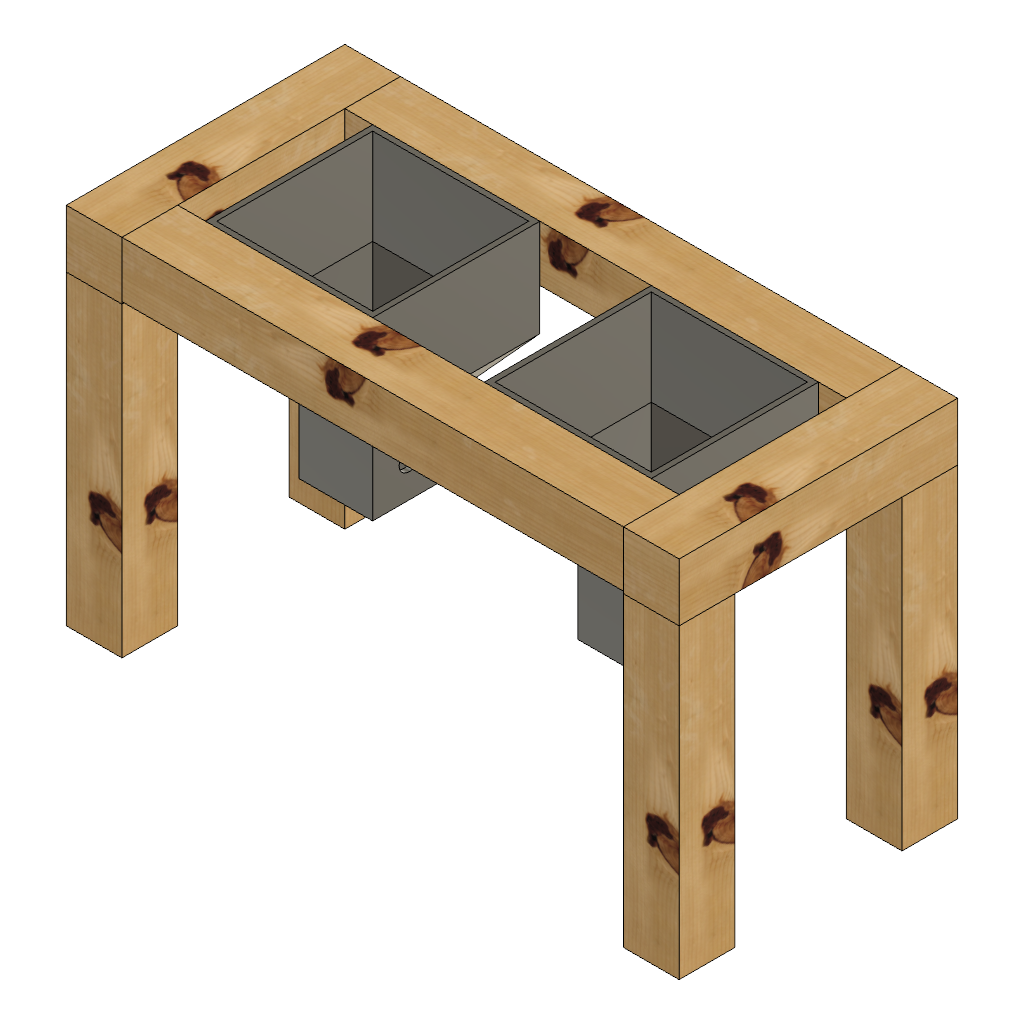
Hopper Mockup (Autodesk Fusion 360 design; units mm, degrees)
Autodesk Fusion 360 part; units mm, degrees
sketch "Sketch1" plane through (0, 0, 0) normal (0, 0, 1) x (1, 0, 0)
  line L0 (-76.2, 76.2) -> (76.2, 76.2)
  line L1 (76.2, 76.2) -> (76.2, -76.2)
  line L2 (76.2, -76.2) -> (-76.2, -76.2)
  line L3 (-76.2, -76.2) -> (-76.2, 76.2)
  line L4 (-76.2, 76.2) -> (76.2, -76.2) construction
  line L5 (76.2, 76.2) -> (-76.2, -76.2) construction
  dimension "d1" = 152.4
  dimension "d2" = 152.4
  constraint horizontal L0
  constraint perpendicular L0 L1
  constraint parallel L0 L2
  constraint parallel L1 L3
  constraint coincident L4 origin
  constraint coincident L5 origin
  measures "d1" distance of L0.start L0.end
  measures "d2" distance of L0.start L2.end
extrude "Extrude1" add sketch "Sketch1" against normal blind 88.9 makes body 1
sketch "Sketch2" plane through (0, 0, -88.9) normal (0, 0, -1) x (1, 0, 0)
  line L0 (76.2, 76.2) -> (-76.2, 76.2)
  line L1 (-76.2, 76.2) -> (-76.2, -76.2)
  line L2 (-76.2, -76.2) -> (76.2, -76.2)
  line L3 (76.2, -76.2) -> (76.2, 76.2)
  line L4 (-76.2, 76.2) -> (76.2, 76.2)
  line L5 (76.2, 76.2) -> (76.2, -76.2)
  line L6 (76.2, -76.2) -> (-76.2, -76.2)
  line L7 (-76.2, -76.2) -> (-76.2, 76.2)
  constraint horizontal L4
  constraint vertical L5
  constraint horizontal L6
  constraint vertical L7
  constraint coincident L2.end L3.start
  constraint coincident L0.end L1.start
extrude "Extrude2" add sketch "Sketch2" along normal blind 50.8 draft -40 bodies 1
sketch "Sketch3" plane through (0, 0, -139.7) normal (0, 0, -1) x (1, 0, 0)
  line L0 (-33.5737, 33.5737) -> (-33.5737, -33.5737)
  line L1 (-33.5737, -33.5737) -> (33.5737, -33.5737)
  line L2 (33.5737, -33.5737) -> (33.5737, 33.5737)
  line L3 (33.5737, 33.5737) -> (-33.5737, 33.5737)
  line L4 (33.5737, -33.5737) -> (-33.5737, -33.5737)
  line L5 (-33.5737, -33.5737) -> (-33.5737, 33.5737)
  line L6 (-33.5737, 33.5737) -> (33.5737, 33.5737)
  line L7 (33.5737, 33.5737) -> (33.5737, -33.5737)
  constraint horizontal L4
  constraint vertical L5
  constraint horizontal L6
  constraint vertical L7
  constraint coincident L0.start L3.end
  constraint coincident L1.end L2.start
extrude "Extrude3" add sketch "Sketch3" along normal blind 63.5 bodies 1
shell "Shell1" thickness 5.08 removed faces 1 at (-25.4, -25.4, 0) on bodies 1
sketch "Sketch4" plane through (33.5737, 0, 0) normal (1, 0, 0) x (0, 1, 0)
  line L0 (33.5737, -139.7) -> (-33.5737, -139.7)
  line L1 (-33.5737, -139.7) -> (-33.5737, -203.2)
  line L2 (-33.5737, -203.2) -> (33.5737, -203.2)
  line L3 (33.5737, -203.2) -> (33.5737, -139.7)
  line L4 (-33.5737, -139.7) -> (33.5737, -203.2) construction
  line L5 (33.5737, -139.7) -> (-33.5737, -203.2) construction
  circle A0 centre (0, -171.45) radius 9.525
  dimension "d10" = 19.05
  constraint coincident L0.end L1.start
  constraint coincident L2.end L3.start
  constraint coincident L0.start L3.end
  constraint coincident L1.end L2.start
  constraint midpoint L4 A0.centre
  measures "d10" diameter of A0
extrude "Extrude4" cut sketch "Sketch4" against normal blind 200.66 contours A0 bodies 1
copy_body "CopyPasteBodies1" bodies 1 makes body 2
move_body "Move1" bodies 2 to x (1, 0, 0) y (0, 1, 0) z (0, 0, 1) at (-254, 0, 0)
sketch "Sketch5" plane through (-330.2, 0, 0) normal (-1, 0, 0) x (0, -1, 0)
  line L0 (76.2, 0) -> (-76.2, 0)
  line L1 (-76.2, 0) -> (-76.2, -88.9)
  line L2 (-76.2, -88.9) -> (76.2, -88.9)
  line L3 (76.2, -88.9) -> (76.2, 0)
  line L4 (-76.2, 0) -> (-127, 0)
  line L5 (-127, 0) -> (-127, -50.8)
  line L6 (-127, -50.8) -> (-76.2, -50.8)
  line L7 (-76.2, -50.8) -> (-76.2, 0)
  dimension "d13" = 50.8
  dimension "d14" = 50.8
  constraint horizontal L4
  constraint vertical L5
  constraint horizontal L6
  constraint vertical L7
  constraint coincident L0.end L1.start
  measures "d13" distance of L0.end L4.end
  measures "d14" distance of L4.end L5.end
extrude "Extrude5" add sketch "Sketch5" along normal blind -431.8 and the other way blind -25.4 separate body contours L1 L4 L5 L6 L7 makes body 3
copy_body "CopyPasteBodies2" bodies 3 makes body 4
move_body "Move2" bodies 4 to x (1, 0, 0) y (0, 1, 0) z (0, 0, 1) at (0, -203.2, 0)
sketch "Sketch6" plane through (0, 127, 0) normal (0, 1, 0) x (-1, 0, 0)
  line L0 (355.6, -50.8) -> (355.6, 0)
  line L1 (355.6, 0) -> (-101.6, 0)
  line L2 (-101.6, 0) -> (-101.6, -50.8)
  line L3 (-101.6, -50.8) -> (355.6, -50.8)
  line L4 (-101.6, 0) -> (-152.4, 0)
  line L5 (-152.4, 0) -> (-152.4, -52.7987)
  line L6 (-152.4, -52.7987) -> (-101.6, -52.7987)
  line L7 (-101.6, -52.7987) -> (-101.6, 0)
  dimension "d17" = 50.8
  constraint horizontal L4
  constraint vertical L5
  constraint horizontal L6
  constraint vertical L7
  constraint coincident L1.end L2.start
  measures "d17" distance of L1.end L4.end
extrude "Extrude6" add sketch "Sketch6" against normal blind 254 separate body contours L2 L4 L5 L6 L7 makes body 5
copy_body "CopyPasteBodies3" bodies 5 makes body 6
move_body "Move3" bodies 6 to x (1, 0, 0) y (0, 1, 0) z (0, 0, 1) at (-508, 0, 0)
sketch "Sketch7" plane through (0, 0, -52.7987) normal (0, 0, -1) x (1, 0, 0)
  line L0 (101.6, -127) -> (152.4, -127)
  line L1 (152.4, -127) -> (152.4, 127)
  line L2 (152.4, 127) -> (101.6, 127)
  line L3 (101.6, 127) -> (101.6, -127)
  line L4 (101.6, 127) -> (152.4, 127)
  line L5 (152.4, 127) -> (152.4, 76.2)
  line L6 (152.4, 76.2) -> (101.6, 76.2)
  line L7 (101.6, 76.2) -> (101.6, 127)
  line L8 (101.6, -76.2) -> (152.4, -76.2)
  line L9 (152.4, -76.2) -> (152.4, -127)
  line L10 (152.4, -127) -> (101.6, -127)
  line L11 (101.6, -127) -> (101.6, -76.2)
  line L12 (-355.6, -76.2) -> (-406.4, -76.2)
  line L13 (-406.4, -76.2) -> (-406.4, -127)
  line L14 (-406.4, -127) -> (-355.6, -127)
  line L15 (-355.6, -127) -> (-355.6, -76.2)
  line L16 (-406.4, 127) -> (-355.6, 127)
  line L17 (-355.6, 127) -> (-355.6, 76.2)
  line L18 (-355.6, 76.2) -> (-406.4, 76.2)
  line L19 (-406.4, 76.2) -> (-406.4, 127)
  constraint horizontal L4
  constraint vertical L5
  constraint horizontal L6
  constraint vertical L7
  constraint coincident L1 L5.end
  constraint coincident L2.end L3.start
  constraint horizontal L8
  constraint vertical L9
  constraint horizontal L10
  constraint vertical L11
  constraint coincident L0.end L1.start
  constraint coincident L3 L8.start
  constraint horizontal L12
  constraint vertical L13
  constraint horizontal L14
  constraint vertical L15
  constraint horizontal L16
  constraint vertical L17
  constraint horizontal L18
  constraint vertical L19
extrude "Extrude7" add sketch "Sketch7" along normal blind 279.4 separate body contours L0 L1 L3 L8 L9 L10 L11 | L1 L2 L3 L4 L5 L6 L7 | L12 L13 L14 L15 | L16 L17 L18 L19 makes body 7 at (118.5333, 127, -145.932) makes body 8 at (-389.4667, -127, -145.932) makes body 9 at (135.4667, -76.2, -145.932) makes body 10 at (-355.6, 110.0667, -145.932)
